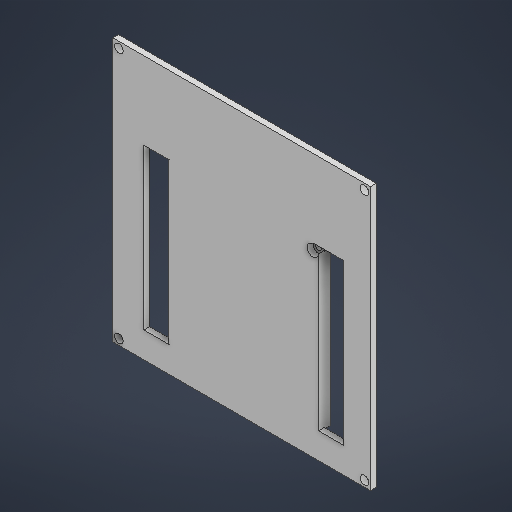
# Autodesk Inventor part: base_stm
Saved by Autodesk Inventor 2027.1 (Build 311270010, 270A)
## iProperties
Created: 2026-10-11
Part Number: base_stm
Material: Generic
Document SubType Name: Modeling
Designer: MineS
Density: 1 g/cm^3
Appearance: Default
Author: MineS
Autodesk Inventor part; units mm, degrees
ref_plane "YZ Plane" through (0, 0, 0) normal (1, 0, 0) x (0, 1, 0)
ref_plane "XZ Plane" through (0, 0, 0) normal (0, 1, 0) x (-1, 0, 0)
ref_plane "XY Plane" through (0, 0, 0) normal (0, 0, 1) x (1, 0, 0)
sketch "Sketch1" plane through (0, 0, 0) normal (0, 0, 1) x (1, 0, 0)
  circle A0 centre (-13.0143, 32.9701) radius 1
  circle A1 centre (35.2457, 34.2401) radius 1
  circle A2 centre (2.2257, -17.8299) radius 1
  line L0 (-13.0143, 32.9701) -> (0, 0) construction
  line L1 (0, 0) -> (2.2257, -17.8299) construction
  line L2 (2.2257, -17.8299) -> (35.2457, 34.2401) construction
  line L3 (0, 0) -> (-9.8559, 0) construction
  circle A3 centre (-13.0143, 32.9701) radius 2
  circle A4 centre (35.2457, 34.2401) radius 2
  circle A5 centre (2.2257, -17.8299) radius 2
  dimension "d1" = 35.4457
  dimension "d2" = 61.6572
  dimension "d3" = 17.9683
  dimension "d4" = 165.575
  dimension "d5" = 39.496
  dimension "d6" = 68.459
  dimension "d7" = 2
  dimension "d8" = 2
  dimension "d9" = 2
  dimension "d10" = 4
  dimension "d11" = 4
  dimension "d12" = 4
  constraints: 8 end point, 6 centre point, 3 coincident, 1 horizontal
  measures "d1" distance of L0.start L0.end
  measures "d2" distance of L1.end L2.end
  measures "d3" distance of L0.end L1.end
  measures "d4" angle of L0 L1
  measures "d5" angle of L1 L2
  measures "d6" angle of L0 L3
  measures "d7" diameter of A0
  measures "d8" diameter of A1
  measures "d9" diameter of A2
  measures "d10" diameter of A3
  measures "d11" diameter of A4
  measures "d12" diameter of A5
extrude "Extrusion1" add sketch "Sketch1" along normal blind 8
sketch "Sketch3" plane through (-13.0143, 32.9701, 8) normal (0, 0, 1) x (1, 0, 0)
  line L0 (-2, 3.27) -> (50.26, 3.27)
  line L1 (50.26, 3.27) -> (50.26, -52.8)
  line L2 (50.26, -52.8) -> (-2, -52.8)
  line L3 (-2, -52.8) -> (-2, 3.27)
  circle A0 centre (0, 0) radius 2 projected
  circle A1 centre (48.26, 1.27) radius 2 projected
  circle A2 centre (15.24, -50.8) radius 2 projected
  point P0 (13.0143, -32.9701)
  point P1 (50.26, 1.27)
  point P2 (48.26, 3.27)
  point P3 (-2, 0)
  point P4 (15.24, -52.8)
  constraints: 8 end point, 4 tangent, 2 perpendicular, 1 horizontal, 1 vertical
extrude "Extrusion3" add sketch "Sketch3" against normal blind 2 contours L0 A1 L1 L2 L3
sketch "Sketch4" plane through (-13.0143, 32.9701, 6) normal (0, 0, -1) x (-1, 0, 0)
  point P0 (-13.0143, -32.9701)
sketch "Sketch5" plane through (0, 0, 8) normal (0, 0, 1) x (1, 0, 0)
  line L0 (-23.7823, -16.3299) -> (-23.7823, 36.5681) projected
  line L1 (46.0137, 36.5681) -> (46.0137, -16.3299) projected
  line L2 (38.062, -21.8536) -> (-15.238, -21.8536) projected
  line L3 (-15.0143, 36.2401) -> (-15.0143, -19.8299) projected
  line L4 (-15.0143, 36.2401) -> (-15.0143, 63.6351)
  line L5 (-15.0143, 32.9701) -> (-15.0143, 36.2401) projected
  line L6 (-15.0143, 63.6351) -> (46.0137, 63.6351)
  line L7 (1.4684, 63.6351) -> (-0.9414, 63.6351) projected
  line L8 (-15.0143, 63.6351) -> (-34.6178, 63.6351)
  line L9 (-34.6178, 63.6351) -> (-34.6178, -28.3649)
  line L10 (-34.6178, -28.3649) -> (55.3822, -28.3649)
  line L11 (55.3822, -28.3649) -> (55.3822, 63.6351)
  line L12 (55.3822, 63.6351) -> (46.0137, 63.6351)
  line L13 (-23.7823, 36.5681) -> (-7.8843, 36.5681) projected
  line L14 (30.6157, 36.5681) -> (46.0137, 36.5681) projected
  line L15 (-23.7823, 36.5681) -> (-15.0143, 36.5681)
  circle A0 centre (35.2457, 34.2401) radius 2 projected
  line L16 (35.2457, 36.2401) -> (35.2457, 36.5681)
  line L17 (35.2457, 36.2401) -> (35.2457, 36.5681)
  line L18 (35.2457, 36.5681) -> (46.0137, 36.5681)
  line L19 (46.0137, 36.5681) -> (46.0137, -16.3299)
  line L20 (46.0137, -16.3299) -> (55.3822, -16.3299)
  line L21 (-23.7823, -16.3299) -> (-23.7823, -19.3299)
  line L22 (-23.7823, -19.3299) -> (46.0137, -19.3299)
  line L23 (46.0137, -19.3299) -> (46.0137, -16.3299)
  line L24 (37.2457, 34.2401) -> (37.2457, -19.8299) projected
  line L25 (37.2457, -19.3299) -> (46.0137, -19.3299)
  line L26 (-15.0143, -19.3299) -> (-23.7823, -19.3299)
  point P0 (0, 0)
  point P1 (-24.816, 63.6351)
  dimension "d20" = 90
  dimension "d21" = 92
  dimension "d22" = 3
  constraints: 36 end point, 10 point on line, 8 perpendicular, 6 collinear, 2 vertical, 1 horizontal, 1 midpoint, 1 point on circle, 1 other
  measures "d20" distance between parallel lines of L11 L9
  measures "d21" distance from line of point (-24.816, 63.635) L10
  measures "d22" distance of L0.start L21.end
extrude "Extrusion4" add sketch "Sketch5" along normal blind 2 contours L21 L22 L23 L20 L11 L10 L9 L8 L4 L13 L0 | L4 L6 L12 L11 L20 L1 L14 L16 A0 L24 L22 L3
sketch "Sketch6" plane through (0, 0, 10) normal (0, 0, 1) x (1, 0, 0)
  circle A0 centre (53.2609, 61.5137) radius 1.5
  circle A1 centre (-32.4965, 61.5137) radius 1.5
  circle A2 centre (-32.4965, -26.2436) radius 1.5
  circle A3 centre (53.2609, -26.2436) radius 1.5
  point P0 (0, 0)
  constraints: 4 centre point, 8 other
extrude "Extrusion5" cut sketch "Sketch6" against normal blind 10
body "Solid1"
